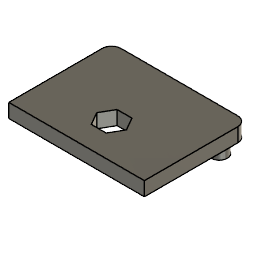
Main body (Autodesk Fusion 360 archive; units mm, degrees)
design "Enclosure"
part number: 2026-04-25-14-46-14-505
Autodesk Fusion 360 part; units mm, degrees
note: some values were not read from the file. Set by a fixed rule: which face or edge a step refers to.
sketch "Sketch1" plane through (0, 0, 0) normal (0, 0, 1) x (1, 0, 0)
  circle A0 centre (14.5, 13.5) radius 12.3
  line L0 (0, 0) -> (0, 40) construction
  line L1 (0, 0) -> (40, 0) construction
  line L2 (0, 0) -> (29, 0)
  line L3 (29, 0) -> (29, 28)
  line L4 (29, 28) -> (0, 28)
  line L5 (0, 28) -> (0, 0)
  dimension "d1" = 24.6
  dimension "d2" = 40
  dimension "d3" = 14.5
  dimension "d4" = 40
  dimension "d5" = 13.5
  dimension "d6" = 28
  dimension "d7" = 29
  constraint coincident L0.start L1.start
  constraint vertical L0
  constraint perpendicular L0 L1
  constraint horizontal L2
  constraint vertical L3
  constraint horizontal L4
  constraint vertical L5
  measures "d1" diameter of A0
  measures "d2" distance of L0.start L0.end
  measures "d3" distance of A0.centre L0
  measures "d4" distance of L0.start L1.end
  measures "d5" distance of A0.centre L1
  measures "d6" distance of L0.start L4.end
  measures "d7" distance of L0 L3
extrude "Extrude1" add sketch "Sketch1" along normal blind 59 makes body 1
fillet "Fillet1" radius 2 2 edges at (0, 28, 29.5) (29, 28, 29.5) on bodies 1
sketch "Sketch2" plane through (0, 28, 0) normal (0, 1, 0) x (-1, 0, 0)
  line L0 (-27, 59) -> (-27, 0)
  line L1 (-27, 0) -> (-2, 0)
  line L2 (-2, 0) -> (-2, 59)
  line L3 (-2, 59) -> (-27, 59)
  line L4 (-2, 59) -> (-27, 0) construction
  line L5 (-2, 0) -> (-27, 59) construction
  circle A0 centre (-14.5, 29.5) radius 7.5
  dimension "d12" = 15
  constraint coincident L2.end L3.start
  constraint coincident L0.end L1.start
  constraint coincident L1.end L2.start
  constraint coincident L0.start L3.end
  constraint midpoint L4 A0.centre
  measures "d12" diameter of A0
extrude "Extrude2" cut sketch "Sketch2" against normal blind 5 contours A0 bodies 1
sketch "Sketch3" plane through (0, 0, 59) normal (0, 0, 1) x (-1, 0, 0)
  circle A0 centre (-14.5, -13.5) radius 12.3
  arc A1 (-29, -26) -> (-27, -28) centre (-27, -26) ccw
  line L0 (-27, -28) -> (-2, -28)
  arc A2 (-2, -28) -> (0, -26) centre (-2, -26) ccw
  line L1 (0, -26) -> (0, 0)
  line L2 (0, 0) -> (-29, 0)
  line L3 (-29, 0) -> (-29, -26)
move_body "Move1" bodies 1 to x (1, 0, 0) y (0, -1, 0) z (0, 0, -1) at (0, 0, 59)
move_body "Move2" bodies 1 to x (-1, 0, 0) y (0, -1, 0) z (0, 0, 1) at (29, 0, 0)
sketch "Sketch4" plane through (0, 0, 59) normal (0, 0, 1) x (-1, 0, 0)
  circle A0 centre (-3, -25) radius 1.75
  line L0 (-27, -28) -> (-2, -28)
  line L1 (0, -26) -> (0, 0)
  line L2 (-14.5, -0.0507) -> (-14.5, -28) construction
  circle A1 centre (-26, -25) radius 1.75
  dimension "d17" = 3.5
  dimension "d18" = 3
  dimension "d19" = 3
  constraint midpoint L0 L2.end
  constraint perpendicular L0 L2
  constraint symmetric A0 L2 A1
  measures "d17" diameter of A0
  measures "d18" distance of A0.centre L0
  measures "d19" distance of A0.centre L1
sketch "Sketch7" plane through (0, 0, 59) normal (0, 0, 1) x (-1, 0, 0)
  circle A0 centre (-3, -25) radius 1.75
  circle A1 centre (-26, -25) radius 1.75
  line L0 (-2, -28) -> (-27, -28)
  line L1 (-29, -27) -> (0, 0) construction
  line L2 (0, -27) -> (-29, 0) construction
  line L3 (0, -28) -> (-29, -28)
  line L4 (-29, -28) -> (-29, -6)
  line L5 (-29, -6) -> (0, -6)
  line L6 (0, -6) -> (0, -28)
  line L7 (-12.9123, -16.25) -> (-11.3246, -13.5)
  line L8 (-11.3246, -13.5) -> (-12.9123, -10.75)
  line L9 (-12.9123, -10.75) -> (-16.0877, -10.75)
  line L10 (-16.0877, -10.75) -> (-17.6754, -13.5)
  line L11 (-17.6754, -13.5) -> (-16.0877, -16.25)
  line L12 (-16.0877, -16.25) -> (-12.9123, -16.25)
  point P0 (-14.5, -13.5)
  dimension "d22" = 3.5
  dimension "d23" = 3.5
  dimension "d35" = 22
  dimension "d36" = 3
  dimension "d37" = 3
  dimension "d38" = 3
  dimension "d39" = 3
  dimension "d40" = 29
  dimension "d42" = 2.75
  constraint coincident L1.end origin
  constraint horizontal L3
  constraint vertical L4
  constraint horizontal L5
  constraint vertical L6
  constraint midpoint L2 P0
  measures "d22" diameter of A0
  measures "d23" diameter of A1
  measures "d35" distance of L3.start L5.end
  measures "d36" distance of A0.centre L3
  measures "d37" distance of A0.centre L6
  measures "d38" distance of A1.centre L3
  measures "d39" distance of A1.centre L4
  measures "d40" distance of L4 L6
  measures "d42" distance of P0 L12
extrude "Extrude4" add sketch "Sketch7" along normal blind 3 separate body contours A0 | A1 | L0 L3 L4 L5 L6 | L7 L8 L9 L10 L11 L12 makes body 2
move_body "Move3" bodies 2 to x (1, 0, 0) y (0, 1, 0) z (0, 0, 1) at (0, 0, 6)
sketch "Sketch8" plane through (0, 0, 65) normal (0, 0, -1) x (1, 0, 0)
  line L0 (29, -6) -> (0, -6)
  line L1 (0, -6) -> (0, -28)
  line L2 (0, -28) -> (29, -28)
  line L3 (29, -28) -> (29, -6)
  circle A0 centre (3, -25) radius 1.75
  circle A1 centre (26, -25) radius 1.75
  line L4 (0, -27) -> (29, 0)
  line L5 (29, -27) -> (0, 0)
  line L6 (16.0877, -10.75) -> (17.6754, -13.5)
  line L7 (17.6754, -13.5) -> (16.0877, -16.25)
  line L8 (16.0877, -16.25) -> (12.9123, -16.25)
  line L9 (12.9123, -16.25) -> (11.3246, -13.5)
  line L10 (11.3246, -13.5) -> (12.9123, -10.75)
  line L11 (12.9123, -10.75) -> (16.0877, -10.75)
extrude "Extrude5" add sketch "Sketch8" along normal blind 3 contours A1 L5 | A1 L5 | A0 L4 | A0 L4 bodies 2
extrude "Extrude6" cut sketch "Sketch8" against normal blind 4 contours L4 L5 L6 L7 | L4 L5 L6 L10 L11 | L4 L5 L9 L10 | L4 L5 L7 L8 L9 bodies 2
fillet "Fillet4" radius 2 2 edges at (29, 28, 66.5) (0, 28, 66.5) on bodies 2
extrude "Extrude7" cut sketch "Sketch7" against normal blind 3 contours A0 | A1 bodies 1
move_body "Move4" bodies 2 to x (1, 0, 0) y (0, 1, 0) z (0, 0, 1) at (0, 0, -2.5)
move_body "Move5" bodies 2 to x (1, 0, 0) y (0, 1, 0) z (0, 0, 1) at (0, 0, -1)
move_body "Move6" bodies 2 to x (1, 0, 0) y (0, 1, 0) z (0, 0, 1) at (0, 0, -2.5)
hidden bodies 1

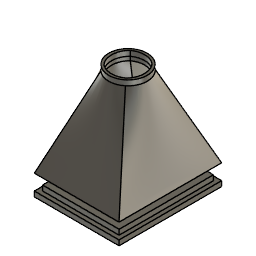
design "Feeder Hopper"
part number: 2026-04-26-10-32-45-579
Autodesk Fusion 360 part; units mm, degrees
sketch "Sketch1" plane through (0, 0, 0) normal (0, 0, 1) x (1, 0, 0)
  line L0 (0, 0) -> (33, 0)
  line L1 (33, 0) -> (33, 40)
  line L2 (33, 40) -> (0, 40)
  line L3 (0, 40) -> (0, 0)
  dimension "d1" = 40
  dimension "d2" = 33
  constraint horizontal L0
  constraint vertical L1
  constraint horizontal L2
  constraint vertical L3
  constraint coincident L0.start L3.end
  measures "d1" distance of L0.start L2.end
  measures "d2" distance of L1 L3
ref_plane "WorkPlane1" through (0, 0, 33) normal (0, 0, 1) x (1, 0, 0)
sketch "Sketch2" plane through (0, 0, 33) normal (0, 0, 1) x (1, 0, 0)
  line L0 (0, 40) -> (33, 0) construction
  line L1 (0, 0) -> (33.9117, 38.8949) construction
  circle A0 centre (16.9558, 19.4475) radius 7.5
  line L2 (25.9558, 7.4475) -> (7.9558, 7.4475)
  line L3 (7.9558, 7.4475) -> (7.9558, 31.4475)
  line L4 (7.9558, 31.4475) -> (25.9558, 31.4475)
  line L5 (25.9558, 31.4475) -> (25.9558, 7.4475)
  line L6 (25.9558, 7.4475) -> (7.9558, 31.4475) construction
  line L7 (7.9558, 7.4475) -> (25.9558, 31.4475) construction
  point P0 (16.9558, 19.4475)
  dimension "d4" = 15
  dimension "d15" = 18
  dimension "d16" = 24
  constraint coincident L1.start origin
  constraint midpoint L1 P0
  constraint horizontal L2
  constraint perpendicular L2 L3
  constraint parallel L2 L4
  constraint parallel L3 L5
  constraint coincident L6 P0
  constraint coincident L7 P0
  constraint coincident P0 A0.centre
  measures "d4" diameter of A0
  measures "d15" distance of L3.end L4.end
  measures "d16" distance of L2.end L3.end
loft "Loft1" add profiles "Sketch1", "Sketch2" section 1 section 2 contours A0 | L2 L3 L4 L5 makes body 1
shell "Shell1" thickness 1.5 removed faces 1 at (22, 26.6667, 0) on bodies 1
extrude "Extrude1" cut 1 faces at (19.5406, 15.86, 31.5) along direction (0, 0, 1) blind 8 on bodies 1 bodies 1
extrude "Extrude2" add 1 faces at (25.5513, 15.8472, 33) along direction (0, 0, 1) blind 2 on bodies 1 bodies 1
ref_plane "WorkPlane2" through (0, 0, -6) normal (0, 0, 1) x (1, 0, 0)
sketch "Sketch3" plane through (0, 0, -6) normal (0, 0, 1) x (1, 0, 0)
  line L0 (1.543, 38.4504) -> (1.543, 1.5377)
  line L1 (1.543, 1.5377) -> (31.4662, 1.5377)
  line L2 (31.4662, 1.5377) -> (31.4662, 38.4504)
  line L3 (31.4662, 38.4504) -> (1.543, 38.4504)
  line L4 (0, 0) -> (0, 40)
  line L5 (0, 40) -> (33, 40)
  line L6 (33, 40) -> (33, 0)
  line L7 (33, 0) -> (0, 0)
sketch "Sketch4" plane through (0, 0, -6) normal (0, 0, 1) x (1, 0, 0)
  line L0 (0, 0) -> (33, 0)
  line L1 (33, 0) -> (33, 40)
  line L2 (33, 40) -> (0, 40)
  line L3 (0, 40) -> (0, 0)
  line L4 (31.4, 1.6) -> (1.6, 1.6)
  line L5 (1.6, 1.6) -> (1.6, 38.4)
  line L6 (1.6, 38.4) -> (31.4, 38.4)
  line L7 (31.4, 38.4) -> (31.4, 1.6)
  line L8 (31.4, 1.6) -> (1.6, 38.4) construction
  line L9 (1.6, 1.6) -> (31.4, 38.4) construction
  point P0 (16.5, 20)
  dimension "d17" = 40
  dimension "d18" = 33
  dimension "d19" = 29.8
  dimension "d20" = 36.8
  constraint horizontal L0
  constraint vertical L1
  constraint horizontal L2
  constraint vertical L3
  constraint coincident L0.start L3.end
  constraint horizontal L4
  constraint perpendicular L4 L5
  constraint parallel L4 L6
  constraint parallel L5 L7
  constraint coincident L8 P0
  constraint coincident L9 P0
  measures "d17" distance of L0.start L2.end
  measures "d18" distance of L0.start L0.end
  measures "d19" distance of L5.end L6.end
  measures "d20" distance of L4.end L5.end
extrude "Extrude5" add sketch "Sketch3" against normal blind 1 separate body contours L0 L1 L2 L3 | L4 L5 L6 L7 makes body 2
extrude "Extrude6" add sketch "Sketch4" along normal blind 1 contours L4 L5 L6 L7 bodies 2
fillet "Fillet1" radius 0.2 4 edges at (25.9558, 19.4475, 35) (16.9558, 31.4475, 35) (7.9558, 19.4475, 35) (16.9558, 7.4475, 35) on bodies 1
move_body "Move1" bodies 2 to x (1, 0, 0) y (0, 1, 0) z (0, 0, 1) at (0, 0, 6)
move_body "Move2" bodies 2 to x (1, 0, 0) y (0, 1, 0) z (0, 0, 1) at (0, 0, -3)

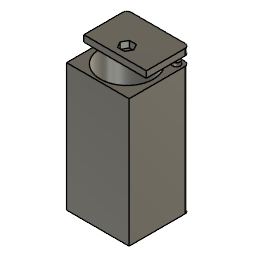
design "Enclosure"
part number: 2026-04-25-14-46-14-505
Autodesk Fusion 360 part; units mm, degrees
sketch "Sketch1" plane through (0, 0, 0) normal (0, 0, 1) x (1, 0, 0)
  circle A0 centre (14.5, 13.5) radius 12.3
  line L0 (0, 0) -> (0, 40) construction
  line L1 (0, 0) -> (40, 0) construction
  line L2 (0, 0) -> (29, 0)
  line L3 (29, 0) -> (29, 28)
  line L4 (29, 28) -> (0, 28)
  line L5 (0, 28) -> (0, 0)
  dimension "d1" = 24.6
  dimension "d2" = 40
  dimension "d3" = 14.5
  dimension "d4" = 40
  dimension "d5" = 13.5
  dimension "d6" = 28
  dimension "d7" = 29
  constraint coincident L0.start L1.start
  constraint vertical L0
  constraint perpendicular L0 L1
  constraint horizontal L2
  constraint vertical L3
  constraint horizontal L4
  constraint vertical L5
  measures "d1" diameter of A0
  measures "d2" distance of L0.start L0.end
  measures "d3" distance of A0.centre L0
  measures "d4" distance of L0.start L1.end
  measures "d5" distance of A0.centre L1
  measures "d6" distance of L0.start L4.end
  measures "d7" distance of L0 L3
extrude "Extrude1" add sketch "Sketch1" along normal blind 59.2 makes body 1
fillet "Fillet1" radius 2 2 edges at (0, 28, 29.6) (29, 28, 29.6) on bodies 1
sketch "Sketch2" plane through (0, 28, 0) normal (0, 1, 0) x (-1, 0, 0)
  line L0 (-27, 59.2) -> (-27, 0)
  line L1 (-27, 0) -> (-2, 0)
  line L2 (-2, 0) -> (-2, 59.2)
  line L3 (-2, 59.2) -> (-27, 59.2)
  line L4 (-2, 59.2) -> (-27, 0) construction
  line L5 (-2, 0) -> (-27, 59.2) construction
  circle A0 centre (-14.5, 29.6) radius 7.5
  line L6 (-5.5, 17.6) -> (-23.5, 17.6)
  line L7 (-23.5, 17.6) -> (-23.5, 41.6)
  line L8 (-23.5, 41.6) -> (-5.5, 41.6)
  line L9 (-5.5, 41.6) -> (-5.5, 17.6)
  line L10 (-5.5, 17.6) -> (-23.5, 41.6) construction
  line L11 (-23.5, 17.6) -> (-5.5, 41.6) construction
  point P0 (-14.5, 29.6)
  dimension "d12" = 15
  dimension "d51" = 18
  dimension "d52" = 24
  constraint coincident L2.end L3.start
  constraint coincident L0.end L1.start
  constraint coincident L1.end L2.start
  constraint coincident L0.start L3.end
  constraint midpoint L4 P0
  constraint horizontal L6
  constraint perpendicular L6 L7
  constraint parallel L6 L8
  constraint parallel L7 L9
  constraint coincident L10 P0
  constraint coincident L11 P0
  constraint coincident P0 A0.centre
  measures "d12" diameter of A0
  measures "d51" distance of L7.end L8.end
  measures "d52" distance of L6.end L7.end
extrude "Extrude2" cut sketch "Sketch2" against normal blind 6 contours A0 | L6 L7 L8 L9 bodies 1
sketch "Sketch3" plane through (0, 0, 59.2) normal (0, 0, 1) x (-1, 0, 0)
  circle A0 centre (-14.5, -13.5) radius 12.3
  arc A1 (-29, -26) -> (-27, -28) centre (-27, -26) ccw
  line L0 (-27, -28) -> (-2, -28)
  arc A2 (-2, -28) -> (0, -26) centre (-2, -26) ccw
  line L1 (0, -26) -> (0, 0)
  line L2 (0, 0) -> (-29, 0)
  line L3 (-29, 0) -> (-29, -26)
move_body "Move1" bodies 1 to x (1, 0, 0) y (0, -1, 0) z (0, 0, -1) at (0, 0, 59)
move_body "Move2" bodies 1 to x (-1, 0, 0) y (0, -1, 0) z (0, 0, 1) at (29, 0, 0)
sketch "Sketch4" plane through (0, 0, 59.2) normal (0, 0, 1) x (-1, 0, 0)
  circle A0 centre (-3, -25) radius 1.75
  line L0 (-27, -28) -> (-2, -28)
  line L1 (0, -26) -> (0, 0)
  line L2 (-14.5, -0.0507) -> (-14.5, -28) construction
  circle A1 centre (-26, -25) radius 1.75
  dimension "d17" = 3.5
  dimension "d18" = 3
  dimension "d19" = 3
  constraint midpoint L0 L2.end
  constraint perpendicular L0 L2
  constraint symmetric A0 L2 A1
  measures "d17" diameter of A0
  measures "d18" distance of A0.centre L0
  measures "d19" distance of A0.centre L1
sketch "Sketch7" plane through (0, 0, 59.2) normal (0, 0, 1) x (-1, 0, 0)
  circle A0 centre (-3, -25) radius 1.75
  circle A1 centre (-26, -25) radius 1.75
  line L0 (-2, -28) -> (-27, -28)
  line L1 (-29, -27) -> (0, 0) construction
  line L2 (0, -27) -> (-29, 0) construction
  line L3 (0, -28) -> (-29, -28)
  line L4 (-29, -28) -> (-29, -8)
  line L5 (-29, -8) -> (0, -8)
  line L6 (0, -8) -> (0, -28)
  line L7 (-12.9123, -16.25) -> (-11.3246, -13.5)
  line L8 (-11.3246, -13.5) -> (-12.9123, -10.75)
  line L9 (-12.9123, -10.75) -> (-16.0877, -10.75)
  line L10 (-16.0877, -10.75) -> (-17.6754, -13.5)
  line L11 (-17.6754, -13.5) -> (-16.0877, -16.25)
  line L12 (-16.0877, -16.25) -> (-12.9123, -16.25)
  point P0 (-14.5, -13.5)
  dimension "d22" = 3.5
  dimension "d23" = 3.5
  dimension "d35" = 20
  dimension "d36" = 3
  dimension "d37" = 3
  dimension "d38" = 3
  dimension "d39" = 3
  dimension "d40" = 29
  dimension "d42" = 2.75
  constraint coincident L1.end origin
  constraint horizontal L3
  constraint vertical L4
  constraint horizontal L5
  constraint vertical L6
  constraint midpoint L2 P0
  measures "d22" diameter of A0
  measures "d23" diameter of A1
  measures "d35" distance of L3.start L5.end
  measures "d36" distance of A0.centre L3
  measures "d37" distance of A0.centre L6
  measures "d38" distance of A1.centre L3
  measures "d39" distance of A1.centre L4
  measures "d40" distance of L4 L6
  measures "d42" distance of P0 L12
extrude "Extrude4" add sketch "Sketch7" along normal blind 3 separate body contours A0 | A1 | L0 L3 L4 L5 L6 | L7 L8 L9 L10 L11 L12 makes body 2
move_body "Move3" bodies 2 to x (1, 0, 0) y (0, 1, 0) z (0, 0, 1) at (0, 0, 6)
sketch "Sketch8" plane through (0, 0, 65.2) normal (0, 0, -1) x (1, 0, 0)
  line L0 (29, -8) -> (0, -8)
  line L1 (0, -8) -> (0, -28)
  line L2 (0, -28) -> (29, -28)
  line L3 (29, -28) -> (29, -8)
  circle A0 centre (3, -25) radius 1.75
  circle A1 centre (26, -25) radius 1.75
  line L4 (0, -27) -> (29, 0)
  line L5 (29, -27) -> (0, 0)
  line L6 (16.0877, -10.75) -> (17.6754, -13.5)
  line L7 (17.6754, -13.5) -> (16.0877, -16.25)
  line L8 (16.0877, -16.25) -> (12.9123, -16.25)
  line L9 (12.9123, -16.25) -> (11.3246, -13.5)
  line L10 (11.3246, -13.5) -> (12.9123, -10.75)
  line L11 (12.9123, -10.75) -> (16.0877, -10.75)
  circle A2 centre (3, -25) radius 1.7
  circle A3 centre (26, -25) radius 1.7
  dimension "d53" = 3.4
  dimension "d54" = 3.4
  constraint concentric A0 A2
  constraint concentric A1 A3
  measures "d53" diameter of A2
  measures "d54" diameter of A3
extrude "Extrude5" add sketch "Sketch8" along normal blind 3 contours L5 A3 | L5 A3 | L4 A2 | L4 A2 bodies 2
extrude "Extrude6" cut sketch "Sketch8" against normal blind 4 contours L4 L5 L6 L7 | L4 L5 L6 L10 L11 | L4 L5 L9 L10 | L4 L5 L7 L8 L9 bodies 2
fillet "Fillet4" radius 2 2 edges at (29, 28, 66.7) (0, 28, 66.7) on bodies 2
extrude "Extrude7" cut sketch "Sketch7" against normal blind 3 contours A0 | A1 bodies 1
move_body "Move4" bodies 2 to x (1, 0, 0) y (0, 1, 0) z (0, 0, 1) at (0, 0, -2.5)
move_body "Move5" bodies 2 to x (1, 0, 0) y (0, 1, 0) z (0, 0, 1) at (0, 0, -1)
move_body "Move6" bodies 2 to x (1, 0, 0) y (0, 1, 0) z (0, 0, 1) at (0, 0, -2.5)
move_body "Move7" bodies 2 to x (1, 0, 0) y (0, 1, 0) z (0, 0, 1) at (0, 0, 6)
fillet "Fillet5" radius 0.5 2 edges at (24.415, 25.6147, 62.2) (1.415, 25.6147, 62.2) on bodies 2
move_body "Move8" bodies 2 to x (1, 0, 0) y (0, 1, 0) z (0, 0, 1) at (0, 0, -6)
move_body "Move9" bodies 2 to x (1, 0, 0) y (0, 1, 0) z (0, 0, 1) at (0, 0, 4)
